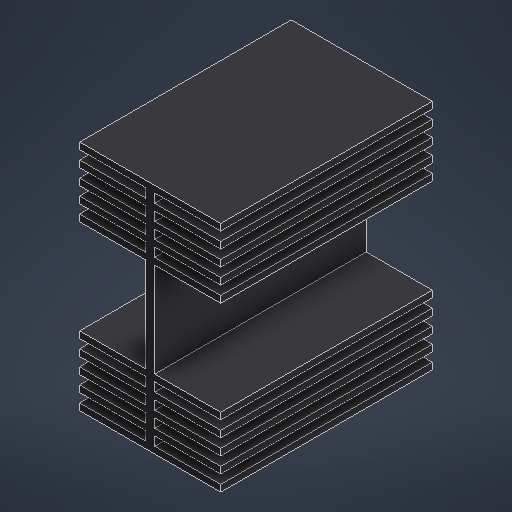
# Autodesk Inventor part: ref_heatsink
Saved by Autodesk Inventor 2027.1 (Build 311270010, 270A)
## iProperties
Created: 2026-10-22
Part Number: ref_heatsink
Material: 일반
Document SubType Name: Modeling
Designer: sungjun
Density: 1 g/cm^3
Appearance: ref_heatsink_c
Author: sungjun
Autodesk Inventor part; units mm, degrees
ref_plane "작업 평면1" through (0, 0, 27.15) normal (0, 0, 1) x (1, 0, 0)
sketch "스케치1" plane through (0, 0, 27.15) normal (0, 0, 1) x (1, 0, 0)
  line L0 (37.2, 33.55) -> (38.8, 33.55)
  line L1 (38.8, 33.55) -> (38.8, 75.45)
  line L2 (38.8, 75.45) -> (37.2, 75.45)
  line L3 (37.2, 75.45) -> (37.2, 33.55)
  constraints: 8 end point, 2 parallel, 1 horizontal, 1 perpendicular
extrude "돌출1" add sketch "스케치1" along normal mid plane 38.1
ref_plane "작업 평면2" through (0, 0, 27.15) normal (0, 0, 1) x (1, 0, 0)
sketch "스케치2" plane through (0, 0, 27.15) normal (0, 0, 1) x (1, 0, 0)
  line L0 (25.3, 33.55) -> (50.7, 33.55)
  line L1 (50.7, 33.55) -> (50.7, 34.75)
  line L2 (50.7, 34.75) -> (25.3, 34.75)
  line L3 (25.3, 34.75) -> (25.3, 33.55)
  constraints: 8 end point, 2 parallel, 1 horizontal, 1 perpendicular
extrude "돌출2" add sketch "스케치2" along normal mid plane 38.1
ref_plane "작업 평면3" through (0, 0, 27.15) normal (0, 0, 1) x (1, 0, 0)
sketch "스케치3" plane through (0, 0, 27.15) normal (0, 0, 1) x (1, 0, 0)
  line L0 (25.3, 36.3625) -> (50.7, 36.3625)
  line L1 (50.7, 36.3625) -> (50.7, 37.5625)
  line L2 (50.7, 37.5625) -> (25.3, 37.5625)
  line L3 (25.3, 37.5625) -> (25.3, 36.3625)
  constraints: 8 end point, 2 parallel, 1 horizontal, 1 perpendicular
extrude "돌출3" add sketch "스케치3" along normal mid plane 38.1
ref_plane "작업 평면4" through (0, 0, 27.15) normal (0, 0, 1) x (1, 0, 0)
sketch "스케치4" plane through (0, 0, 27.15) normal (0, 0, 1) x (1, 0, 0)
  line L0 (25.3, 39.175) -> (50.7, 39.175)
  line L1 (50.7, 39.175) -> (50.7, 40.375)
  line L2 (50.7, 40.375) -> (25.3, 40.375)
  line L3 (25.3, 40.375) -> (25.3, 39.175)
  constraints: 8 end point, 2 parallel, 1 horizontal, 1 perpendicular
extrude "돌출4" add sketch "스케치4" along normal mid plane 38.1
ref_plane "작업 평면5" through (0, 0, 27.15) normal (0, 0, 1) x (1, 0, 0)
sketch "스케치5" plane through (0, 0, 27.15) normal (0, 0, 1) x (1, 0, 0)
  line L0 (25.3, 41.9875) -> (50.7, 41.9875)
  line L1 (50.7, 41.9875) -> (50.7, 43.1875)
  line L2 (50.7, 43.1875) -> (25.3, 43.1875)
  line L3 (25.3, 43.1875) -> (25.3, 41.9875)
  constraints: 8 end point, 2 parallel, 1 horizontal, 1 perpendicular
extrude "돌출5" add sketch "스케치5" along normal mid plane 38.1
ref_plane "작업 평면6" through (0, 0, 27.15) normal (0, 0, 1) x (1, 0, 0)
sketch "스케치6" plane through (0, 0, 27.15) normal (0, 0, 1) x (1, 0, 0)
  line L0 (25.3, 44.8) -> (50.7, 44.8)
  line L1 (50.7, 44.8) -> (50.7, 46)
  line L2 (50.7, 46) -> (25.3, 46)
  line L3 (25.3, 46) -> (25.3, 44.8)
  constraints: 8 end point, 2 parallel, 1 horizontal, 1 perpendicular
extrude "돌출6" add sketch "스케치6" along normal mid plane 38.1
ref_plane "작업 평면7" through (0, 0, 27.15) normal (0, 0, 1) x (1, 0, 0)
sketch "스케치7" plane through (0, 0, 27.15) normal (0, 0, 1) x (1, 0, 0)
  line L0 (25.3, 74.25) -> (50.7, 74.25)
  line L1 (50.7, 74.25) -> (50.7, 75.45)
  line L2 (50.7, 75.45) -> (25.3, 75.45)
  line L3 (25.3, 75.45) -> (25.3, 74.25)
  constraints: 8 end point, 2 parallel, 1 horizontal, 1 perpendicular
extrude "돌출7" add sketch "스케치7" along normal mid plane 38.1
ref_plane "작업 평면8" through (0, 0, 27.15) normal (0, 0, 1) x (1, 0, 0)
sketch "스케치8" plane through (0, 0, 27.15) normal (0, 0, 1) x (1, 0, 0)
  line L0 (25.3, 71.4375) -> (50.7, 71.4375)
  line L1 (50.7, 71.4375) -> (50.7, 72.6375)
  line L2 (50.7, 72.6375) -> (25.3, 72.6375)
  line L3 (25.3, 72.6375) -> (25.3, 71.4375)
  constraints: 8 end point, 2 parallel, 1 horizontal, 1 perpendicular
extrude "돌출8" add sketch "스케치8" along normal mid plane 38.1
ref_plane "작업 평면9" through (0, 0, 27.15) normal (0, 0, 1) x (1, 0, 0)
sketch "스케치9" plane through (0, 0, 27.15) normal (0, 0, 1) x (1, 0, 0)
  line L0 (25.3, 68.625) -> (50.7, 68.625)
  line L1 (50.7, 68.625) -> (50.7, 69.825)
  line L2 (50.7, 69.825) -> (25.3, 69.825)
  line L3 (25.3, 69.825) -> (25.3, 68.625)
  constraints: 8 end point, 2 parallel, 1 horizontal, 1 perpendicular
extrude "돌출9" add sketch "스케치9" along normal mid plane 38.1
ref_plane "작업 평면10" through (0, 0, 27.15) normal (0, 0, 1) x (1, 0, 0)
sketch "스케치10" plane through (0, 0, 27.15) normal (0, 0, 1) x (1, 0, 0)
  line L0 (25.3, 65.8125) -> (50.7, 65.8125)
  line L1 (50.7, 65.8125) -> (50.7, 67.0125)
  line L2 (50.7, 67.0125) -> (25.3, 67.0125)
  line L3 (25.3, 67.0125) -> (25.3, 65.8125)
  constraints: 8 end point, 2 parallel, 1 horizontal, 1 perpendicular
extrude "돌출10" add sketch "스케치10" along normal mid plane 38.1
ref_plane "작업 평면11" through (0, 0, 27.15) normal (0, 0, 1) x (1, 0, 0)
sketch "스케치11" plane through (0, 0, 27.15) normal (0, 0, 1) x (1, 0, 0)
  line L0 (25.3, 63) -> (50.7, 63)
  line L1 (50.7, 63) -> (50.7, 64.2)
  line L2 (50.7, 64.2) -> (25.3, 64.2)
  line L3 (25.3, 64.2) -> (25.3, 63)
  constraints: 8 end point, 2 parallel, 1 horizontal, 1 perpendicular
extrude "돌출11" add sketch "스케치11" along normal mid plane 38.1
